Autodesk Fusion 360 part; units mm, degrees
(part 2 of 2)
equation "L1oct_FirstNotch = ( L1oct_Length - ( L1oct_Notches - 1 ) * NotchCenters ) / 2" comment "Centre of the first notch (keeps the row of notches centred)"
equation "L1oct_NotchStep = NotchCenters * min(1; L1oct_Notches - 1) + 0.001 mm * ( 1 - min(1; L1oct_Notches - 1) )" comment "Pattern step: NotchCenters, or about zero when there is only one notch"
equation "d65 = LogDia / 2"
equation "d66 = PrintFlat"
equation "d67 = LogDia / 2"
equation "d68 = LogDia - PrintFlat"
equation "d69 = L1oct_Length"
equation "d71 = LogDia * ( 1 - sqrt(2) / 2 )"
equation "d72 = LogDia / 2 + 1 mm"
equation "d73 = PrintFlat + 1 mm"
equation "d74 = LogDia / 2 + 1 mm"
equation "d75 = L1oct_Length"
equation "d77 = L1oct_FirstNotch - NotchWidth / 2"
equation "d78 = LogDia / 2 - NotchDepth"
equation "d79 = L1oct_FirstNotch + NotchWidth / 2"
equation "d80 = LogDia / 2 + 1 mm"
equation "d81 = L1oct_FirstNotch - NotchWidth / 2"
equation "d82 = LogDia / 2 - NotchDepth"
equation "d83 = L1oct_FirstNotch + NotchWidth / 2"
equation "d84 = LogDia / 2 + 1 mm"
equation "d85 = LogDia"
equation "d87 = max(L1oct_Notches; 2)"
equation "d89 = L1oct_NotchStep"
equation "L2a_Length = 4.5 in" comment "Overall length"
equation "L2a_Notches = 2" comment "Number of notch positions"
equation "L2a_FirstNotch = ( L2a_Length - ( L2a_Notches - 1 ) * NotchCenters ) / 2" comment "Centre of the first notch (keeps the row of notches centred)"
equation "L2a_NotchStep = NotchCenters * min(1; L2a_Notches - 1) + 0.001 mm * ( 1 - min(1; L2a_Notches - 1) )" comment "Pattern step: NotchCenters, or about zero when there is only one notch"
equation "d95 = LogDia / 2 - PrintFlat"
equation "d96 = LogDia"
equation "d97 = L2a_Length"
equation "d99 = L2a_FirstNotch - NotchWidth / 2"
equation "d100 = LogDia / 2 - NotchDepth"
equation "d101 = L2a_FirstNotch + NotchWidth / 2"
equation "d102 = LogDia / 2 + 1 mm"
equation "d103 = L2a_FirstNotch - NotchWidth / 2"
equation "d104 = LogDia / 2 - NotchDepth"
equation "d105 = L2a_FirstNotch + NotchWidth / 2"
equation "d106 = LogDia / 2 + 1 mm"
equation "d107 = LogDia"
equation "d109 = max(L2a_Notches; 2)"
equation "d111 = L2a_NotchStep"
equation "L3_Length = 7.625 in" comment "Overall length"
equation "L3_Notches = 3" comment "Number of notch positions"
equation "L3_FirstNotch = ( L3_Length - ( L3_Notches - 1 ) * NotchCenters ) / 2" comment "Centre of the first notch (keeps the row of notches centred)"
equation "L3_NotchStep = NotchCenters * min(1; L3_Notches - 1) + 0.001 mm * ( 1 - min(1; L3_Notches - 1) )" comment "Pattern step: NotchCenters, or about zero when there is only one notch"
equation "d117 = LogDia / 2 - PrintFlat"
equation "d118 = LogDia"
equation "d119 = L3_Length"
equation "d121 = L3_FirstNotch - NotchWidth / 2"
equation "d122 = LogDia / 2 - NotchDepth"
equation "d123 = L3_FirstNotch + NotchWidth / 2"
equation "d124 = LogDia / 2 + 1 mm"
equation "d125 = L3_FirstNotch - NotchWidth / 2"
equation "d126 = LogDia / 2 - NotchDepth"
equation "d127 = L3_FirstNotch + NotchWidth / 2"
equation "d128 = LogDia / 2 + 1 mm"
equation "d129 = LogDia"
equation "d131 = max(L3_Notches; 2)"
equation "d133 = L3_NotchStep"
equation "L4_Length = 10.625 in" comment "Overall length"
equation "L4_Notches = 4" comment "Number of notch positions"
equation "L4_FirstNotch = ( L4_Length - ( L4_Notches - 1 ) * NotchCenters ) / 2" comment "Centre of the first notch (keeps the row of notches centred)"
equation "L4_NotchStep = NotchCenters * min(1; L4_Notches - 1) + 0.001 mm * ( 1 - min(1; L4_Notches - 1) )" comment "Pattern step: NotchCenters, or about zero when there is only one notch"
equation "d139 = LogDia / 2 - PrintFlat"
equation "d140 = LogDia"
equation "d141 = L4_Length"
equation "d143 = L4_FirstNotch - NotchWidth / 2"
equation "d144 = LogDia / 2 - NotchDepth"
equation "d145 = L4_FirstNotch + NotchWidth / 2"
equation "d146 = LogDia / 2 + 1 mm"
equation "d147 = L4_FirstNotch - NotchWidth / 2"
equation "d148 = LogDia / 2 - NotchDepth"
equation "d149 = L4_FirstNotch + NotchWidth / 2"
equation "d150 = LogDia / 2 + 1 mm"
equation "d151 = LogDia"
equation "d153 = max(L4_Notches; 2)"
equation "d155 = L4_NotchStep"
equation "Half2_Length = 4.5 in" comment "Overall length"
equation "Half2_Notches = 2" comment "Number of notch positions"
equation "Half2_FirstNotch = ( Half2_Length - ( Half2_Notches - 1 ) * NotchCenters ) / 2" comment "Centre of the first notch (keeps the row of notches centred)"
equation "Half2_NotchStep = NotchCenters * min(1; Half2_Notches - 1) + 0.001 mm * ( 1 - min(1; Half2_Notches - 1) )" comment "Pattern step: NotchCenters, or about zero when there is only one notch"
equation "d161 = HalfLogHeight - LogDia / 2"
equation "d162 = LogDia"
equation "d163 = Half2_Length"
equation "d165 = LogDia / 2 + 1 mm"
equation "d167 = LogDia / 2 - PrintFlat"
equation "d168 = HalfLogHeight + 1 mm"
equation "d169 = Half2_Length"
equation "d171 = Half2_FirstNotch - NotchWidth / 2"
equation "d172 = HalfLogHeight - NotchDepth"
equation "d173 = Half2_FirstNotch + NotchWidth / 2"
equation "d174 = HalfLogHeight + 1 mm"
equation "d175 = LogDia + 2 mm"
equation "d177 = max(Half2_Notches; 2)"
equation "d179 = Half2_NotchStep"
equation "Half3_Length = 7.5 in" comment "Overall length"
equation "Half3_Notches = 3" comment "Number of notch positions"
equation "Half3_FirstNotch = ( Half3_Length - ( Half3_Notches - 1 ) * NotchCenters ) / 2" comment "Centre of the first notch (keeps the row of notches centred)"
equation "Half3_NotchStep = NotchCenters * min(1; Half3_Notches - 1) + 0.001 mm * ( 1 - min(1; Half3_Notches - 1) )" comment "Pattern step: NotchCenters, or about zero when there is only one notch"
equation "d185 = HalfLogHeight - LogDia / 2"
equation "d186 = LogDia"
equation "d187 = Half3_Length"
equation "d189 = LogDia / 2 + 1 mm"
equation "d191 = LogDia / 2 - PrintFlat"
equation "d192 = HalfLogHeight + 1 mm"
equation "d193 = Half3_Length"
equation "d195 = Half3_FirstNotch - NotchWidth / 2"
equation "d196 = HalfLogHeight - NotchDepth"
equation "d197 = Half3_FirstNotch + NotchWidth / 2"
equation "d198 = HalfLogHeight + 1 mm"
equation "d199 = LogDia + 2 mm"
equation "d201 = max(Half3_Notches; 2)"
equation "d203 = Half3_NotchStep"
equation "BevShort_Length = 1.5 in" comment "Length along the long edge"
equation "BevShort_Angle = 39 deg" comment "Angle of the slanted end (roof pitch of the wooden triangle)"
equation "d207 = LogDia / 2 - PrintFlat"
equation "d208 = LogDia"
equation "d209 = BevShort_Length"
equation "d211 = BevShort_Length"
equation "d212 = LogDia / 2"
equation "d213 = LogDia / 2"
equation "d214 = BevShort_Length - LogDia / tan(BevShort_Angle)"
equation "d215 = LogDia"
equation "Solid1_Length = 1.375 in" comment "Length"
equation "d218 = LogDia"
equation "d219 = Solid1_Length"
equation "Solid2_Length = 1.625 in" comment "Length"
equation "d222 = LogDia"
equation "d223 = Solid2_Length"
equation "GableL_Width = 8.5 in" comment "Overall width"
equation "GableL_Notches = 3" comment "Number of notch positions"
equation "GableL_FirstNotch = ( GableL_Width - ( GableL_Notches - 1 ) * NotchCenters ) / 2" comment "Centre of the first notch (keeps the row of notches centred)"
equation "GableL_NotchStep = NotchCenters * min(1; GableL_Notches - 1) + 0.001 mm * ( 1 - min(1; GableL_Notches - 1) )" comment "Pattern step: NotchCenters, or about zero when there is only one notch"
equation "GableL_Steps = 7" comment "Roof steps per side"
equation "GableL_EaveHeight = 7.5 mm" comment "Height of the slope start above the base"
equation "GableL_LipThk = 5.4 mm" comment "Eave lip thickness"
equation "GableL_LipHeight = 3.6 mm" comment "Eave lip height above the slope start"
equation "GableL_Riser = 2.9 mm" comment "Vertical riser of each roof step"
equation "GableL_Height = 2.25 in" comment "Overall height at the peak"
equation "GableL_StepRun = ( GableL_Width / 2 - GableL_LipThk ) / GableL_Steps" comment "Horizontal run of one step"
equation "GableL_TreadRise = ( GableL_Height - GableL_EaveHeight - ( GableL_Steps - 1 ) * GableL_Riser ) / GableL_Steps" comment "Rise of one sloped tread"
equation "GableL_StepPitch = sqrt(GableL_StepRun ^ 2 + ( GableL_TreadRise + GableL_Riser ) ^ 2)" comment "Step spacing measured along the slope"
equation "PlasticRoofAngle = atan(( GableL_Height + GableL_Riser - GableL_EaveHeight ) / ( GableL_Width / 2 - GableL_LipThk ))" comment "Pitch of the large plastic gable. The small gable and the chimney follow it"
equation "GableS_Width = 5.8 in" comment "Overall width"
equation "GableS_Notches = 2" comment "Number of notch positions"
equation "GableS_FirstNotch = ( GableS_Width - ( GableS_Notches - 1 ) * NotchCenters ) / 2" comment "Centre of the first notch (keeps the row of notches centred)"
equation "GableS_NotchStep = NotchCenters * min(1; GableS_Notches - 1) + 0.001 mm * ( 1 - min(1; GableS_Notches - 1) )" comment "Pattern step: NotchCenters, or about zero when there is only one notch"
equation "GableS_Steps = 5" comment "Roof steps per side"
equation "GableS_EaveHeight = 7.5 mm" comment "Height of the slope start above the base"
equation "GableS_LipThk = 5.4 mm" comment "Eave lip thickness"
equation "GableS_LipHeight = 3.6 mm" comment "Eave lip height above the slope start"
equation "GableS_Riser = 2.9 mm" comment "Vertical riser of each roof step"
equation "GableS_Height = GableS_EaveHeight + tan(PlasticRoofAngle) * ( GableS_Width / 2 - GableS_LipThk ) - GableS_Riser" comment "Overall height at the peak"
equation "GableS_StepRun = ( GableS_Width / 2 - GableS_LipThk ) / GableS_Steps" comment "Horizontal run of one step"
equation "GableS_TreadRise = ( GableS_Height - GableS_EaveHeight - ( GableS_Steps - 1 ) * GableS_Riser ) / GableS_Steps" comment "Rise of one sloped tread"
equation "GableS_StepPitch = sqrt(GableS_StepRun ^ 2 + ( GableS_TreadRise + GableS_Riser ) ^ 2)" comment "Step spacing measured along the slope"
equation "d252 = GableL_Width / 2"
equation "d253 = GableL_Height + GableL_Riser"
equation "d254 = GableL_LipThk"
equation "d255 = GableL_EaveHeight"
equation "d256 = GableL_EaveHeight + GableL_LipHeight"
equation "d257 = GableThk"
equation "d259 = GableL_LipThk"
equation "d260 = GableL_EaveHeight"
equation "d261 = GableL_LipThk + GableL_StepRun"
equation "d262 = GableL_EaveHeight + GableL_TreadRise + GableL_Riser"
equation "d263 = GableL_EaveHeight + GableL_TreadRise"
equation "d264 = GableThk"
equation "d266 = GableL_Steps"
equation "d268 = GableL_StepPitch"
equation "d270 = GableL_Width / 2"
equation "d274 = GableL_FirstNotch - NotchWidth / 2"
equation "d276 = GableL_FirstNotch + NotchWidth / 2"
equation "d277 = NotchDepth"
equation "d278 = GableThk"
equation "d280 = max(GableL_Notches; 2)"
equation "d282 = GableL_NotchStep"
equation "d284 = GableS_Width / 2"
equation "d285 = GableS_Height + GableS_Riser"
equation "d286 = GableS_LipThk"
equation "d287 = GableS_EaveHeight"
equation "d288 = GableS_EaveHeight + GableS_LipHeight"
equation "d289 = GableThk"
equation "d291 = GableS_LipThk"
equation "d292 = GableS_EaveHeight"
equation "d293 = GableS_LipThk + GableS_StepRun"
equation "d294 = GableS_EaveHeight + GableS_TreadRise + GableS_Riser"
equation "d295 = GableS_EaveHeight + GableS_TreadRise"
equation "d296 = GableThk"
equation "d298 = GableS_Steps"
equation "d300 = GableS_StepPitch"
equation "d302 = GableS_Width / 2"
equation "d306 = GableS_FirstNotch - NotchWidth / 2"
equation "d308 = GableS_FirstNotch + NotchWidth / 2"
equation "d309 = NotchDepth"
equation "d310 = GableThk"
equation "d312 = max(GableS_Notches; 2)"
equation "d314 = GableS_NotchStep"
equation "GableTri_Width = 4.875 in" comment "Overall width"
equation "GableTri_Notches = 2" comment "Number of notch positions"
equation "GableTri_FirstNotch = ( GableTri_Width - ( GableTri_Notches - 1 ) * NotchCenters ) / 2" comment "Centre of the first notch (keeps the row of notches centred)"
equation "GableTri_NotchStep = NotchCenters * min(1; GableTri_Notches - 1) + 0.001 mm * ( 1 - min(1; GableTri_Notches - 1) )" comment "Pattern step: NotchCenters, or about zero when there is only one notch"
equation "GableTri_Height = 2 in" comment "Height at the peak"
equation "d321 = GableTri_Width"
equation "d322 = GableTri_Width / 2"
equation "d323 = GableTri_Height"
equation "d324 = GableThk"
equation "d326 = GableTri_FirstNotch - NotchWidth / 2"
equation "d328 = GableTri_FirstNotch + NotchWidth / 2"
equation "d329 = NotchDepth"
equation "d330 = GableThk"
equation "d332 = max(GableTri_Notches; 2)"
equation "d334 = GableTri_NotchStep"
equation "ShFlat6_Length = 6 in" comment "Length"
equation "d337 = FlatShingleWidth / 2"
equation "d338 = ShFlat6_Length"
equation "d339 = FlatShingleWidth / 2"
equation "d340 = ShingleThk"
equation "ShFlat9_Length = 9 in" comment "Length"
equation "d343 = FlatShingleWidth / 2"
equation "d344 = ShFlat9_Length"
equation "d345 = FlatShingleWidth / 2"
equation "d346 = ShingleThk"
equation "ShFlat11_Length = 11 in" comment "Length"
equation "d349 = FlatShingleWidth / 2"
equation "d350 = ShFlat11_Length"
equation "d351 = FlatShingleWidth / 2"
equation "d352 = ShingleThk"
equation "ShRidge5_Length = 5.625 in" comment "Length"
equation "d355 = RidgeShingleWidth / 2"
equation "d356 = ShRidge5_Length"
equation "d357 = RidgeShingleWidth / 2"
equation "d358 = ShingleThk"
equation "d360 = RidgeGrooveWidth / 2"
equation "d361 = ShingleThk"
equation "d362 = RidgeGrooveWidth / 2"
equation "d363 = ShingleThk - RidgeGrooveDepth"
equation "d364 = ShRidge5_Length"
equation "ShRidge6_Length = 6 in" comment "Length"
equation "d367 = RidgeShingleWidth / 2"
equation "d368 = ShRidge6_Length"
equation "d369 = RidgeShingleWidth / 2"
equation "d370 = ShingleThk"
equation "d372 = RidgeGrooveWidth / 2"
equation "d373 = ShingleThk"
equation "d374 = RidgeGrooveWidth / 2"
equation "d375 = ShingleThk - RidgeGrooveDepth"
equation "d376 = ShRidge6_Length"
equation "ShRidge9_Length = 9 in" comment "Length"
equation "d379 = RidgeShingleWidth / 2"
equation "d380 = ShRidge9_Length"
equation "d381 = RidgeShingleWidth / 2"
equation "d382 = ShingleThk"
equation "d384 = RidgeGrooveWidth / 2"
equation "d385 = ShingleThk"
equation "d386 = RidgeGrooveWidth / 2"
equation "d387 = ShingleThk - RidgeGrooveDepth"
equation "d388 = ShRidge9_Length"
equation "Chimney_Width = 1.375 in" comment "Width across the ridge"
equation "Chimney_Depth = 1 in" comment "Depth along the ridge"
equation "Chimney_Height = 1.2 in" comment "Overall height"
equation "Chimney_Wall = 0.12 in" comment "Wall thickness of the open top"
equation "Chimney_Pocket = 0.5 in" comment "Depth of the open top"
equation "Chimney_VDepth = Chimney_Width / 2 * tan(PlasticRoofAngle)" comment "Depth of the V cut that straddles the ridge"
equation "d396 = Chimney_Width / 2"
equation "d397 = Chimney_Depth / 2"
equation "d398 = Chimney_Width / 2"
equation "d399 = Chimney_Depth / 2"
equation "d400 = Chimney_Height"
equation "d402 = Chimney_Width / 2 - Chimney_Wall"
equation "d403 = Chimney_Depth / 2 - Chimney_Wall"
equation "d404 = Chimney_Width / 2 - Chimney_Wall"
equation "d405 = Chimney_Depth / 2 - Chimney_Wall"
equation "d406 = Chimney_Pocket"
equation "d408 = Chimney_Width / 2"
equation "d409 = Chimney_Height"
equation "d410 = Chimney_Width / 2"
equation "d411 = Chimney_Height - Chimney_VDepth"
equation "d412 = Chimney_Depth + 2 mm"
equation "Door_Courses = 4" comment "Log courses the panel spans"
equation "Door_Width = NotchCenters - LogDia - 2 * Clearance" comment "Width (fits the gap between crossing logs)"
equation "Door_Height = ( Door_Courses - 1 ) * CourseRise + LogDia - 2 * Clearance" comment "Height"
equation "d417 = Door_Width / 2"
equation "d418 = Door_Height / 2"
equation "d419 = Door_Width / 2"
equation "d420 = Door_Height / 2"
equation "d421 = PanelThk"
equation "Window_Courses = 3" comment "Log courses the panel spans"
equation "Window_Width = NotchCenters - LogDia - 2 * Clearance" comment "Width (fits the gap between crossing logs)"
equation "Window_Height = ( Window_Courses - 1 ) * CourseRise + LogDia - 2 * Clearance" comment "Height"
equation "Window_OpeningWidth = 1.125 in" comment "Opening width"
equation "Window_OpeningHeight = 0.625 in" comment "Opening height"
equation "d428 = Window_Width / 2"
equation "d429 = Window_Height / 2"
equation "d430 = Window_Width / 2"
equation "d431 = Window_Height / 2"
equation "d432 = Window_OpeningWidth / 2"
equation "d433 = Window_OpeningHeight / 2"
equation "d434 = Window_OpeningWidth / 2"
equation "d435 = Window_OpeningHeight / 2"
equation "d436 = PanelThk"
named bodies: "log_1insert_1-5_8", "log_1insert_1-1_2_round", "log_1insert_1-1_2_octagonal", "log_2insert_4-1_2", "log_3insert_7-5_8", "log_4insert_10-5_8", "half_log_4-1_2", "half_log_7-1_2", "beveled_end_1-1_2", "solid_log_1-3_8", "solid_log_1-5_8", "gable_plastic_8-1_2", "gable_plastic_small_2notch", "gable_wood_triangle_4x2", "shingle_flat_6", "shingle_flat_9", "shingle_flat_11", "shingle_ridge_5-5_8", "shingle_ridge_6", "shingle_ridge_9", "chimney", "extra_door", "extra_window"
